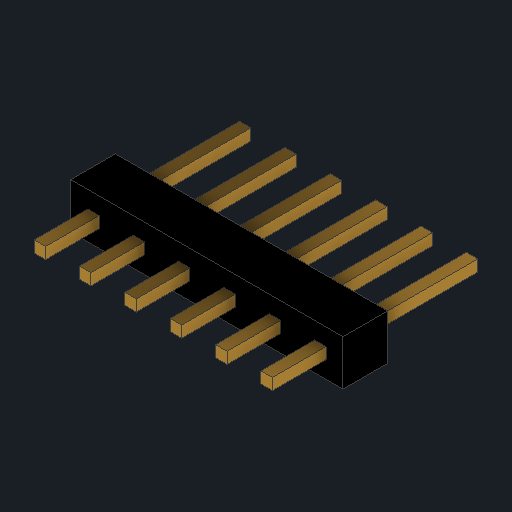
# Autodesk Inventor part: Header 1x6 (TCS3448)
Saved by Autodesk Inventor 2027.2 (Build 312334000, 334)
## iProperties
Created: 2026-11-06
Part Number: Header 1x6 (TCS3448)
Material: Generic
Description: 1x6 0.1in male header under the TCS3448 breakout (plastic spacer 2.5 mm)
Document SubType Name: Modeling
Designer: isaac
Density: 1 g/cm^3
Appearance: Default
Author: isaac
Autodesk Inventor part; units mm, degrees
ref_plane "YZ Plane" through (0, 0, 0) normal (1, 0, 0) x (0, 1, 0)
ref_plane "XZ Plane" through (0, 0, 0) normal (0, 1, 0) x (-1, 0, 0)
sketch "Sketch1" plane through (0, 0, 0) normal (0, 0, 1) x (1, 0, 0)
  line L0 (5.08, 1.27) -> (20.32, 1.27)
  line L1 (20.32, 1.27) -> (20.32, 3.81)
  line L2 (20.32, 3.81) -> (5.08, 3.81)
  line L3 (5.08, 3.81) -> (5.08, 1.27)
  constraints: 8 end point, 2 parallel, 1 horizontal, 1 perpendicular
extrude "Plastic" add sketch "Sketch1" against normal blind 2.5
ref_plane "Work Plane1" through (0, 0, -2.5) normal (0, 0, 1) x (1, 0, 0)
sketch "Sketch2" plane through (0, 0, -2.5) normal (0, 0, 1) x (1, 0, 0)
  line L0 (6.03, 2.22) -> (6.67, 2.22)
  line L1 (6.67, 2.22) -> (6.67, 2.86)
  line L2 (6.67, 2.86) -> (6.03, 2.86)
  line L3 (6.03, 2.86) -> (6.03, 2.22)
  line L4 (8.57, 2.22) -> (9.21, 2.22)
  line L5 (9.21, 2.22) -> (9.21, 2.86)
  line L6 (9.21, 2.86) -> (8.57, 2.86)
  line L7 (8.57, 2.86) -> (8.57, 2.22)
  line L8 (11.11, 2.22) -> (11.75, 2.22)
  line L9 (11.75, 2.22) -> (11.75, 2.86)
  line L10 (11.75, 2.86) -> (11.11, 2.86)
  line L11 (11.11, 2.86) -> (11.11, 2.22)
  line L12 (13.65, 2.22) -> (14.29, 2.22)
  line L13 (14.29, 2.22) -> (14.29, 2.86)
  line L14 (14.29, 2.86) -> (13.65, 2.86)
  line L15 (13.65, 2.86) -> (13.65, 2.22)
  line L16 (16.19, 2.22) -> (16.83, 2.22)
  line L17 (16.83, 2.22) -> (16.83, 2.86)
  line L18 (16.83, 2.86) -> (16.19, 2.86)
  line L19 (16.19, 2.86) -> (16.19, 2.22)
  line L20 (18.73, 2.22) -> (19.37, 2.22)
  line L21 (19.37, 2.22) -> (19.37, 2.86)
  line L22 (19.37, 2.86) -> (18.73, 2.86)
  line L23 (18.73, 2.86) -> (18.73, 2.22)
  constraints: 48 end point, 12 parallel, 6 horizontal, 6 perpendicular
extrude "Pins long end" add sketch "Sketch2" against normal blind 6
sketch "Sketch3" plane through (0, 0, 0) normal (0, 0, 1) x (1, 0, 0)
  line L0 (6.03, 2.22) -> (6.67, 2.22)
  line L1 (6.67, 2.22) -> (6.67, 2.86)
  line L2 (6.67, 2.86) -> (6.03, 2.86)
  line L3 (6.03, 2.86) -> (6.03, 2.22)
  line L4 (8.57, 2.22) -> (9.21, 2.22)
  line L5 (9.21, 2.22) -> (9.21, 2.86)
  line L6 (9.21, 2.86) -> (8.57, 2.86)
  line L7 (8.57, 2.86) -> (8.57, 2.22)
  line L8 (11.11, 2.22) -> (11.75, 2.22)
  line L9 (11.75, 2.22) -> (11.75, 2.86)
  line L10 (11.75, 2.86) -> (11.11, 2.86)
  line L11 (11.11, 2.86) -> (11.11, 2.22)
  line L12 (13.65, 2.22) -> (14.29, 2.22)
  line L13 (14.29, 2.22) -> (14.29, 2.86)
  line L14 (14.29, 2.86) -> (13.65, 2.86)
  line L15 (13.65, 2.86) -> (13.65, 2.22)
  line L16 (16.19, 2.22) -> (16.83, 2.22)
  line L17 (16.83, 2.22) -> (16.83, 2.86)
  line L18 (16.83, 2.86) -> (16.19, 2.86)
  line L19 (16.19, 2.86) -> (16.19, 2.22)
  line L20 (18.73, 2.22) -> (19.37, 2.22)
  line L21 (19.37, 2.22) -> (19.37, 2.86)
  line L22 (19.37, 2.86) -> (18.73, 2.86)
  line L23 (18.73, 2.86) -> (18.73, 2.22)
  constraints: 48 end point, 12 parallel, 6 horizontal, 6 perpendicular
extrude "Pins short end" add sketch "Sketch3" along normal blind 3
sketch "Sketch4" plane through (0, 0, 0) normal (0, 0, 1) x (1, 0, 0)
  line L0 (6.03, 2.22) -> (6.67, 2.22)
  line L1 (6.67, 2.22) -> (6.67, 2.86)
  line L2 (6.67, 2.86) -> (6.03, 2.86)
  line L3 (6.03, 2.86) -> (6.03, 2.22)
  line L4 (8.57, 2.22) -> (9.21, 2.22)
  line L5 (9.21, 2.22) -> (9.21, 2.86)
  line L6 (9.21, 2.86) -> (8.57, 2.86)
  line L7 (8.57, 2.86) -> (8.57, 2.22)
  line L8 (11.11, 2.22) -> (11.75, 2.22)
  line L9 (11.75, 2.22) -> (11.75, 2.86)
  line L10 (11.75, 2.86) -> (11.11, 2.86)
  line L11 (11.11, 2.86) -> (11.11, 2.22)
  line L12 (13.65, 2.22) -> (14.29, 2.22)
  line L13 (14.29, 2.22) -> (14.29, 2.86)
  line L14 (14.29, 2.86) -> (13.65, 2.86)
  line L15 (13.65, 2.86) -> (13.65, 2.22)
  line L16 (16.19, 2.22) -> (16.83, 2.22)
  line L17 (16.83, 2.22) -> (16.83, 2.86)
  line L18 (16.83, 2.86) -> (16.19, 2.86)
  line L19 (16.19, 2.86) -> (16.19, 2.22)
  line L20 (18.73, 2.22) -> (19.37, 2.22)
  line L21 (19.37, 2.22) -> (19.37, 2.86)
  line L22 (19.37, 2.86) -> (18.73, 2.86)
  line L23 (18.73, 2.86) -> (18.73, 2.22)
  constraints: 48 end point, 12 parallel, 6 horizontal, 6 perpendicular
extrude "Pins in plastic" add sketch "Sketch4" against normal blind 2.5
body "Solid1"
